driver-gear-12t (Autodesk Fusion 360 design; units mm, degrees)
part number: 2026-11-14-17-19-38-524
part number: 2026-11-14-17-20-11-877
Autodesk Fusion 360 part; units mm, degrees
(part 1 of 5)
sketch "Sketch1" plane through (0, 0, 0) normal (0, 0, 1) x (1, 0, 0) in component "Component"
  spline S0 degree 5 poles (5.75544, -0.790203) (5.755494, -0.79021) (5.755609, -0.790225) (5.755801, -0.790248) (5.756096, -0.790283) (5.756529, -0.790332) (5.757027, -0.790387) (5.75759, -0.790448) (5.758217, -0.790513) (5.758907, -0.790584) (5.75966, -0.790657) (5.760476, -0.790735) (5.761353, -0.790815) (5.762292, -0.790897) (5.763291, -0.790981) (5.764351, -0.791067) (5.765472, -0.791154) (5.766651, -0.791242) (5.767891, -0.79133) (5.769189, -0.791419) (5.770545, -0.791506) (5.771959, -0.791593) (5.773431, -0.791679) (5.77496, -0.791762) (5.776545, -0.791844) (5.778187, -0.791924) (5.779885, -0.792001) (5.781639, -0.792074) (5.783447, -0.792144) (5.785311, -0.792211) (5.787228, -0.792273) (5.7892, -0.79233) (5.791225, -0.792383) (5.793304, -0.792431) (5.795436, -0.792473) (5.79762, -0.792509) (5.799856, -0.79254) (5.802144, -0.792563) (5.804483, -0.79258) (5.806874, -0.79259) (5.809315, -0.792593) (5.811807, -0.792587) (5.814349, -0.792574) (5.816941, -0.792553) (5.819582, -0.792523) (5.822272, -0.792484) (5.825011, -0.792436) (5.827798, -0.792379) (5.830634, -0.792312) (5.833517, -0.792235) (5.836448, -0.792148) (5.839426, -0.792051) (5.84245, -0.791942) (5.845522, -0.791823) (5.848639, -0.791693) (5.851802, -0.791551) (5.855011, -0.791398) (5.858266, -0.791232) (5.861565, -0.791054) (5.864909, -0.790864) (5.868298, -0.790662) (5.87173, -0.790446) (5.875207, -0.790217) (5.878727, -0.789975) (5.88229, -0.789719) (5.885896, -0.78945) (5.889545, -0.789166) (5.893237, -0.788869) (5.89697, -0.788557) (5.900746, -0.78823) (5.904563, -0.787888) (5.908421, -0.787532) (5.91232, -0.78716) (5.91626, -0.786772) (5.920241, -0.786369) (5.924262, -0.78595) (5.928323, -0.785515) (5.932423, -0.785064) (5.936563, -0.784596) (5.940743, -0.784112) (5.944961, -0.783611) (5.949218, -0.783093) (5.953513, -0.782558) (5.957847, -0.782005) (5.962218, -0.781435) (5.966627, -0.780847) (5.971074, -0.780241) (5.975557, -0.779618) (5.980078, -0.778976) (5.984635, -0.778316) (5.989229, -0.777637) (5.993859, -0.776939) (5.998525, -0.776223) (6.003227, -0.775487) (6.007964, -0.774733) (6.012736, -0.773959) (6.017544, -0.773166) (6.022386, -0.772353) (6.027263, -0.77152) (6.032174, -0.770667) (6.037119, -0.769794) (6.042098, -0.768901) (6.047111, -0.767987) (6.052157, -0.767053) (6.057236, -0.766099) (6.062348, -0.765123) (6.067493, -0.764127) (6.072671, -0.763109) (6.077881, -0.762071) (6.083122, -0.76101) (6.088396, -0.759929) (6.093701, -0.758826) (6.099038, -0.757701) (6.104406, -0.756554) (6.109805, -0.755385) (6.115235, -0.754194) (6.120695, -0.752981) (6.126185, -0.751746) (6.131706, -0.750488) (6.137257, -0.749207) (6.142837, -0.747904) (6.148447, -0.746578) (6.154086, -0.745229) (6.159754, -0.743856) (6.165452, -0.742461) (6.171177, -0.741042) (6.176932, -0.7396) (6.182714, -0.738135) (6.188525, -0.736646) (6.194363, -0.735133) (6.20023, -0.733596) (6.206123, -0.732035) (6.212044, -0.73045) (6.217992, -0.728842) (6.223967, -0.727208) (6.229969, -0.725551) (6.235997, -0.723869) (6.242051, -0.722162) (6.248132, -0.720431) (6.254238, -0.718675) (6.26037, -0.716895) (6.266528, -0.715089) (6.272711, -0.713258) (6.278919, -0.711403) (6.285152, -0.709522) (6.29141, -0.707615) (6.297692, -0.705684) (6.303999, -0.703726) (6.31033, -0.701744) (6.316685, -0.699735) (6.323064, -0.697701) (6.329466, -0.695642) (6.335892, -0.693556) (6.342342, -0.691444) (6.348814, -0.689306) (6.355309, -0.687142) (6.361827, -0.684952) (6.368368, -0.682736) (6.374931, -0.680493) (6.381516, -0.678224) (6.388123, -0.675928) (6.394752, -0.673606) (6.401403, -0.671257) (6.408075, -0.668881) (6.414769, -0.666478) (6.421483, -0.664049) (6.428219, -0.661592) (6.434975, -0.659109) (6.441752, -0.656598) (6.44855, -0.654061) (6.455368, -0.651496) (6.462205, -0.648904) (6.469063, -0.646284) (6.475941, -0.643637) (6.482838, -0.640963) (6.489755, -0.63826) (6.49669, -0.635531) (6.503645, -0.632773) (6.510619, -0.629988) (6.517612, -0.627176) (6.524623, -0.624335) (6.531653, -0.621466) (6.5387, -0.61857) (6.545766, -0.615645) (6.55285, -0.612692) (6.559952, -0.609711) (6.567071, -0.606702) (6.574208, -0.603665) (6.581362, -0.6006) (6.588533, -0.597506) (6.595721, -0.594383) (6.602926, -0.591232) (6.610147, -0.588053) (6.617385, -0.584845) (6.624639, -0.581609) (6.63191, -0.578344) (6.639196, -0.57505) (6.646498, -0.571727) (6.653816, -0.568376) (6.66115, -0.564995) (6.668499, -0.561586) (6.675863, -0.558148) (6.683242, -0.554681) (6.690636, -0.551185) (6.698044, -0.54766) (6.705468, -0.544106) (6.712905, -0.540522) (6.720357, -0.53691) (6.727824, -0.533268) (6.735304, -0.529597) (6.742798, -0.525897) (6.750305, -0.522167) (6.757827, -0.518408) (6.765361, -0.514619) (6.772909, -0.510801) (6.78047, -0.506954) (6.788044, -0.503077) (6.79563, -0.49917) (6.80323, -0.495234) (6.810841, -0.491268) (6.818465, -0.487273) (6.826102, -0.483247) (6.83375, -0.479192) (6.84141, -0.475108) (6.849082, -0.470993) (6.856766, -0.466849) (6.864461, -0.462675) (6.872167, -0.458471) (6.879885, -0.454236) (6.887613, -0.449973) (6.895353, -0.445679) (6.903103, -0.441355) (6.910864, -0.437001) (6.918635, -0.432617) (6.926417, -0.428203) (6.934209, -0.423758) (6.942011, -0.419284) (6.949822, -0.41478) (6.957643, -0.410245) (6.965474, -0.40568) (6.973315, -0.401085) (6.979595, -0.397385) (6.984309, -0.394596) (6.987454, -0.39273) (6.989027, -0.391796) knots 0 0 0 0 0 0 0.00416667 0.00833333 0.0125 0.01666667 0.02083333 0.025 0.02916667 0.03333333 0.0375 0.04166667 0.04583333 0.05 0.05416667 0.05833333 0.0625 0.06666667 0.07083333 0.075 0.07916667 0.08333333 0.0875 0.09166667 0.09583333 0.1 0.10416667 0.10833333 0.1125 0.11666667 0.12083333 0.125 0.12916667 0.13333333 0.1375 0.14166667 0.14583333 0.15 0.15416667 0.15833333 0.1625 0.16666667 0.17083333 0.175 0.17916667 0.18333333 0.1875 0.19166667 0.19583333 0.2 0.20416667 0.20833333 0.2125 0.21666667 0.22083333 0.225 0.22916667 0.23333333 0.2375 0.24166667 0.24583333 0.25 0.25416667 0.25833333 0.2625 0.26666667 0.27083333 0.275 0.27916667 0.28333333 0.2875 0.29166667 0.29583333 0.3 0.30416667 0.30833333 0.3125 0.31666667 0.32083333 0.325 0.32916667 0.33333333 0.3375 0.34166667 0.34583333 0.35 0.35416667 0.35833333 0.3625 0.36666667 0.37083333 0.375 0.37916667 0.38333333 0.3875 0.39166667 0.39583333 0.4 0.40416667 0.40833333 0.4125 0.41666667 0.42083333 0.425 0.42916667 0.43333333 0.4375 0.44166667 0.44583333 0.45 0.45416667 0.45833333 0.4625 0.46666667 0.47083333 0.475 0.47916667 0.48333333 0.4875 0.49166667 0.49583333 0.5 0.50416667 0.50833333 0.5125 0.51666667 0.52083333 0.525 0.52916667 0.53333333 0.5375 0.54166667 0.54583333 0.55 0.55416667 0.55833333 0.5625 0.56666667 0.57083333 0.575 0.57916667 0.58333333 0.5875 0.59166667 0.59583333 0.6 0.60416667 0.60833333 0.6125 0.61666667 0.62083333 0.625 0.62916667 0.63333333 0.6375 0.64166667 0.64583333 0.65 0.65416667 0.65833333 0.6625 0.66666667 0.67083333 0.675 0.67916667 0.68333333 0.6875 0.69166667 0.69583333 0.7 0.70416667 0.70833333 0.7125 0.71666667 0.72083333 0.725 0.72916667 0.73333333 0.7375 0.74166667 0.74583333 0.75 0.75416667 0.75833333 0.7625 0.76666667 0.77083333 0.775 0.77916667 0.78333333 0.7875 0.79166667 0.79583333 0.8 0.80416667 0.80833333 0.8125 0.81666667 0.82083333 0.825 0.82916667 0.83333333 0.8375 0.84166667 0.84583333 0.85 0.85416667 0.85833333 0.8625 0.86666667 0.87083333 0.875 0.87916667 0.88333333 0.8875 0.89166667 0.89583333 0.9 0.90416667 0.90833333 0.9125 0.91666667 0.92083333 0.925 0.92916667 0.93333333 0.9375 0.94166667 0.94583333 0.95 0.95416667 0.95833333 0.9625 0.96666667 0.97083333 0.975 0.97916667 0.98333333 0.9875 0.99166667 0.99583333 1 1 1 1 1 1
  spline S1 degree 5 poles (5.75544, 0.790203) (5.755494, 0.79021) (5.755609, 0.790225) (5.755801, 0.790248) (5.756096, 0.790283) (5.756529, 0.790332) (5.757027, 0.790387) (5.75759, 0.790448) (5.758217, 0.790513) (5.758907, 0.790584) (5.75966, 0.790657) (5.760476, 0.790735) (5.761353, 0.790815) (5.762292, 0.790897) (5.763291, 0.790981) (5.764351, 0.791067) (5.765472, 0.791154) (5.766651, 0.791242) (5.767891, 0.79133) (5.769189, 0.791419) (5.770545, 0.791506) (5.771959, 0.791593) (5.773431, 0.791679) (5.77496, 0.791762) (5.776545, 0.791844) (5.778187, 0.791924) (5.779885, 0.792001) (5.781639, 0.792074) (5.783447, 0.792144) (5.785311, 0.792211) (5.787228, 0.792273) (5.7892, 0.79233) (5.791225, 0.792383) (5.793304, 0.792431) (5.795436, 0.792473) (5.79762, 0.792509) (5.799856, 0.79254) (5.802144, 0.792563) (5.804483, 0.79258) (5.806874, 0.79259) (5.809315, 0.792593) (5.811807, 0.792587) (5.814349, 0.792574) (5.816941, 0.792553) (5.819582, 0.792523) (5.822272, 0.792484) (5.825011, 0.792436) (5.827798, 0.792379) (5.830634, 0.792312) (5.833517, 0.792235) (5.836448, 0.792148) (5.839426, 0.792051) (5.84245, 0.791942) (5.845522, 0.791823) (5.848639, 0.791693) (5.851802, 0.791551) (5.855011, 0.791398) (5.858266, 0.791232) (5.861565, 0.791054) (5.864909, 0.790864) (5.868298, 0.790662) (5.87173, 0.790446) (5.875207, 0.790217) (5.878727, 0.789975) (5.88229, 0.789719) (5.885896, 0.78945) (5.889545, 0.789166) (5.893237, 0.788869) (5.89697, 0.788557) (5.900746, 0.78823) (5.904563, 0.787888) (5.908421, 0.787532) (5.91232, 0.78716) (5.91626, 0.786772) (5.920241, 0.786369) (5.924262, 0.78595) (5.928323, 0.785515) (5.932423, 0.785064) (5.936563, 0.784596) (5.940743, 0.784112) (5.944961, 0.783611) (5.949218, 0.783093) (5.953513, 0.782558) (5.957847, 0.782005) (5.962218, 0.781435) (5.966627, 0.780847) (5.971074, 0.780241) (5.975557, 0.779618) (5.980078, 0.778976) (5.984635, 0.778316) (5.989229, 0.777637) (5.993859, 0.776939) (5.998525, 0.776223) (6.003227, 0.775487) (6.007964, 0.774733) (6.012736, 0.773959) (6.017544, 0.773166) (6.022386, 0.772353) (6.027263, 0.77152) (6.032174, 0.770667) (6.037119, 0.769794) (6.042098, 0.768901) (6.047111, 0.767987) (6.052157, 0.767053) (6.057236, 0.766099) (6.062348, 0.765123) (6.067493, 0.764127) (6.072671, 0.763109) (6.077881, 0.762071) (6.083122, 0.76101) (6.088396, 0.759929) (6.093701, 0.758826) (6.099038, 0.757701) (6.104406, 0.756554) (6.109805, 0.755385) (6.115235, 0.754194) (6.120695, 0.752981) (6.126185, 0.751746) (6.131706, 0.750488) (6.137257, 0.749207) (6.142837, 0.747904) (6.148447, 0.746578) (6.154086, 0.745229) (6.159754, 0.743856) (6.165452, 0.742461) (6.171177, 0.741042) (6.176932, 0.7396) (6.182714, 0.738135) (6.188525, 0.736646) (6.194363, 0.735133) (6.20023, 0.733596) (6.206123, 0.732035) (6.212044, 0.73045) (6.217992, 0.728842) (6.223967, 0.727208) (6.229969, 0.725551) (6.235997, 0.723869) (6.242051, 0.722162) (6.248132, 0.720431) (6.254238, 0.718675) (6.26037, 0.716895) (6.266528, 0.715089) (6.272711, 0.713258) (6.278919, 0.711403) (6.285152, 0.709522) (6.29141, 0.707615) (6.297692, 0.705684) (6.303999, 0.703726) (6.31033, 0.701744) (6.316685, 0.699735) (6.323064, 0.697701) (6.329466, 0.695642) (6.335892, 0.693556) (6.342342, 0.691444) (6.348814, 0.689306) (6.355309, 0.687142) (6.361827, 0.684952) (6.368368, 0.682736) (6.374931, 0.680493) (6.381516, 0.678224) (6.388123, 0.675928) (6.394752, 0.673606) (6.401403, 0.671257) (6.408075, 0.668881) (6.414769, 0.666478) (6.421483, 0.664049) (6.428219, 0.661592) (6.434975, 0.659109) (6.441752, 0.656598) (6.44855, 0.654061) (6.455368, 0.651496) (6.462205, 0.648904) (6.469063, 0.646284) (6.475941, 0.643637) (6.482838, 0.640963) (6.489755, 0.63826) (6.49669, 0.635531) (6.503645, 0.632773) (6.510619, 0.629988) (6.517612, 0.627176) (6.524623, 0.624335) (6.531653, 0.621466) (6.5387, 0.61857) (6.545766, 0.615645) (6.55285, 0.612692) (6.559952, 0.609711) (6.567071, 0.606702) (6.574208, 0.603665) (6.581362, 0.6006) (6.588533, 0.597506) (6.595721, 0.594383) (6.602926, 0.591232) (6.610147, 0.588053) (6.617385, 0.584845) (6.624639, 0.581609) (6.63191, 0.578344) (6.639196, 0.57505) (6.646498, 0.571727) (6.653816, 0.568376) (6.66115, 0.564995) (6.668499, 0.561586) (6.675863, 0.558148) (6.683242, 0.554681) (6.690636, 0.551185) (6.698044, 0.54766) (6.705468, 0.544106) (6.712905, 0.540522) (6.720357, 0.53691) (6.727824, 0.533268) (6.735304, 0.529597) (6.742798, 0.525897) (6.750305, 0.522167) (6.757827, 0.518408) (6.765361, 0.514619) (6.772909, 0.510801) (6.78047, 0.506954) (6.788044, 0.503077) (6.79563, 0.49917) (6.80323, 0.495234) (6.810841, 0.491268) (6.818465, 0.487273) (6.826102, 0.483247) (6.83375, 0.479192) (6.84141, 0.475108) (6.849082, 0.470993) (6.856766, 0.466849) (6.864461, 0.462675) (6.872167, 0.458471) (6.879885, 0.454236) (6.887613, 0.449973) (6.895353, 0.445679) (6.903103, 0.441355) (6.910864, 0.437001) (6.918635, 0.432617) (6.926417, 0.428203) (6.934209, 0.423758) (6.942011, 0.419284) (6.949822, 0.41478) (6.957643, 0.410245) (6.965474, 0.40568) (6.973315, 0.401085) (6.979595, 0.397385) (6.984309, 0.394596) (6.987454, 0.39273) (6.989027, 0.391796) knots 0 0 0 0 0 0 0.00416667 0.00833333 0.0125 0.01666667 0.02083333 0.025 0.02916667 0.03333333 0.0375 0.04166667 0.04583333 0.05 0.05416667 0.05833333 0.0625 0.06666667 0.07083333 0.075 0.07916667 0.08333333 0.0875 0.09166667 0.09583333 0.1 0.10416667 0.10833333 0.1125 0.11666667 0.12083333 0.125 0.12916667 0.13333333 0.1375 0.14166667 0.14583333 0.15 0.15416667 0.15833333 0.1625 0.16666667 0.17083333 0.175 0.17916667 0.18333333 0.1875 0.19166667 0.19583333 0.2 0.20416667 0.20833333 0.2125 0.21666667 0.22083333 0.225 0.22916667 0.23333333 0.2375 0.24166667 0.24583333 0.25 0.25416667 0.25833333 0.2625 0.26666667 0.27083333 0.275 0.27916667 0.28333333 0.2875 0.29166667 0.29583333 0.3 0.30416667 0.30833333 0.3125 0.31666667 0.32083333 0.325 0.32916667 0.33333333 0.3375 0.34166667 0.34583333 0.35 0.35416667 0.35833333 0.3625 0.36666667 0.37083333 0.375 0.37916667 0.38333333 0.3875 0.39166667 0.39583333 0.4 0.40416667 0.40833333 0.4125 0.41666667 0.42083333 0.425 0.42916667 0.43333333 0.4375 0.44166667 0.44583333 0.45 0.45416667 0.45833333 0.4625 0.46666667 0.47083333 0.475 0.47916667 0.48333333 0.4875 0.49166667 0.49583333 0.5 0.50416667 0.50833333 0.5125 0.51666667 0.52083333 0.525 0.52916667 0.53333333 0.5375 0.54166667 0.54583333 0.55 0.55416667 0.55833333 0.5625 0.56666667 0.57083333 0.575 0.57916667 0.58333333 0.5875 0.59166667 0.59583333 0.6 0.60416667 0.60833333 0.6125 0.61666667 0.62083333 0.625 0.62916667 0.63333333 0.6375 0.64166667 0.64583333 0.65 0.65416667 0.65833333 0.6625 0.66666667 0.67083333 0.675 0.67916667 0.68333333 0.6875 0.69166667 0.69583333 0.7 0.70416667 0.70833333 0.7125 0.71666667 0.72083333 0.725 0.72916667 0.73333333 0.7375 0.74166667 0.74583333 0.75 0.75416667 0.75833333 0.7625 0.76666667 0.77083333 0.775 0.77916667 0.78333333 0.7875 0.79166667 0.79583333 0.8 0.80416667 0.80833333 0.8125 0.81666667 0.82083333 0.825 0.82916667 0.83333333 0.8375 0.84166667 0.84583333 0.85 0.85416667 0.85833333 0.8625 0.86666667 0.87083333 0.875 0.87916667 0.88333333 0.8875 0.89166667 0.89583333 0.9 0.90416667 0.90833333 0.9125 0.91666667 0.92083333 0.925 0.92916667 0.93333333 0.9375 0.94166667 0.94583333 0.95 0.95416667 0.95833333 0.9625 0.96666667 0.97083333 0.975 0.97916667 0.98333333 0.9875 0.99166667 0.99583333 1 1 1 1 1 1
  spline S2 degree 5 poles (5.754897, -0.790134) (5.754919, -0.790137) (5.754962, -0.790142) (5.755028, -0.79015) (5.755114, -0.790162) (5.755223, -0.790175) (5.75531, -0.790187) (5.755375, -0.790195) (5.755418, -0.7902) (5.75544, -0.790203) knots 0 0 0 0 0 0 0.2 0.4 0.6 0.8 1 1 1 1 1 1
  spline S3 degree 5 poles (5.754897, 0.790134) (5.754919, 0.790137) (5.754962, 0.790142) (5.755028, 0.79015) (5.755114, 0.790162) (5.755223, 0.790175) (5.75531, 0.790187) (5.755375, 0.790195) (5.755418, 0.7902) (5.75544, 0.790203) knots 0 0 0 0 0 0 0.2 0.4 0.6 0.8 1 1 1 1 1 1
  line L0 (0, 0) -> (5.754897, -0.790134)
  line L1 (0, 0) -> (5.754897, 0.790134)
  arc A0 (6.989027, -0.391796) -> (6.989027, 0.391796) centre (0, 0) ccw
  point P0 (5.75707, -0.790392)
  point P1 (5.75979, -0.790669)
  point P2 (5.763604, -0.791006)
  point P3 (5.768513, -0.791372)
  point P4 (5.774519, -0.791737)
  point P5 (5.781621, -0.792072)
  point P6 (5.789821, -0.792346)
  point P7 (5.799117, -0.792529)
  point P8 (5.809509, -0.79259)
  point P9 (5.820994, -0.792501)
  point P10 (5.833571, -0.792231)
  point P11 (5.847237, -0.79175)
  point P12 (5.861986, -0.791029)
  point P13 (5.877817, -0.790036)
  point P14 (5.894723, -0.788743)
  point P15 (5.912699, -0.78712)
  point P16 (5.931739, -0.785137)
  point P17 (5.951837, -0.782765)
  point P18 (5.972984, -0.779974)
  point P19 (5.995174, -0.776735)
  point P20 (6.018398, -0.77302)
  point P21 (6.042646, -0.768798)
  point P22 (6.067908, -0.764042)
  point P23 (6.094176, -0.758723)
  point P24 (6.121436, -0.752811)
  point P25 (6.149679, -0.74628)
  point P26 (6.178892, -0.739101)
  point P27 (6.209063, -0.731246)
  point P28 (6.240177, -0.722688)
  point P29 (6.272222, -0.713399)
  point P30 (6.305182, -0.703353)
  point P31 (6.339044, -0.692521)
  point P32 (6.373791, -0.680879)
  point P33 (6.409407, -0.668399)
  point P34 (6.445876, -0.655056)
  point P35 (6.483181, -0.640824)
  point P36 (6.521303, -0.625677)
  point P37 (6.560225, -0.609591)
  point P38 (6.599928, -0.592541)
  point P39 (6.640392, -0.574502)
  point P40 (6.681597, -0.55545)
  point P41 (6.723524, -0.535362)
  point P42 (6.766151, -0.514215)
  point P43 (6.809457, -0.491985)
  point P44 (6.85342, -0.46865)
  point P45 (6.898018, -0.444188)
  point P46 (6.943228, -0.418577)
  point P47 (5.75707, 0.790392)
  point P48 (5.75979, 0.790669)
  point P49 (5.763604, 0.791006)
  point P50 (5.768513, 0.791372)
  point P51 (5.774519, 0.791737)
  point P52 (5.781621, 0.792072)
  point P53 (5.789821, 0.792346)
  point P54 (5.799117, 0.792529)
  point P55 (5.809509, 0.79259)
  point P56 (5.820994, 0.792501)
  point P57 (5.833571, 0.792231)
  point P58 (5.847237, 0.79175)
  point P59 (5.861986, 0.791029)
  point P60 (5.877817, 0.790036)
  point P61 (5.894723, 0.788743)
  point P62 (5.912699, 0.78712)
  point P63 (5.931739, 0.785137)
  point P64 (5.951837, 0.782765)
  point P65 (5.972984, 0.779974)
  point P66 (5.995174, 0.776735)
  point P67 (6.018398, 0.77302)
  point P68 (6.042646, 0.768798)
  point P69 (6.067908, 0.764042)
  point P70 (6.094176, 0.758723)
  point P71 (6.121436, 0.752811)
  point P72 (6.149679, 0.74628)
  point P73 (6.178892, 0.739101)
  point P74 (6.209063, 0.731246)
  point P75 (6.240177, 0.722688)
  point P76 (6.272222, 0.713399)
  point P77 (6.305182, 0.703353)
  point P78 (6.339044, 0.692521)
  point P79 (6.373791, 0.680879)
  point P80 (6.409407, 0.668399)
  point P81 (6.445876, 0.655056)
  point P82 (6.483181, 0.640824)
  point P83 (6.521303, 0.625677)
  point P84 (6.560225, 0.609591)
  point P85 (6.599928, 0.592541)
  point P86 (6.640392, 0.574502)
  point P87 (6.681597, 0.55545)
  point P88 (6.723524, 0.535362)
  point P89 (6.766151, 0.514215)
  point P90 (6.809457, 0.491985)
  point P91 (6.85342, 0.46865)
  point P92 (6.898018, 0.444188)
  point P93 (6.943228, 0.418577)
sketch "Sketch2" plane through (0, 0, 0) normal (0, 0, 1) x (1, 0, 0) in component "Component"
  circle A0 centre (0, 0) radius 4.75
extrude "Extrude1" add sketch "Sketch2" along normal blind 6 contours A0 picked at (0.37743, 0.961676) makes body 1 in component "Component"
extrude "Extrude2" add sketch "Sketch1" along normal blind 6 separate body contours S0 S1 L0 L1 A0 picked at (3.83696, 0) makes body 2 in component "Component"
pattern_circular "C-Pattern1" count 12 over 360 about axis through (0, 0, 1.75) along (0, 0, 1) of "Extrude2" makes body 3 at (1.793153, 0.731128, 2) makes body 4 at (0.731128, 1.793153, 2) makes body 5 at (0.263401, 1.91848, 2) makes body 6 at (-0.731128, 1.793153, 2) makes body 7 at (-1.793153, 0.731128, 2) makes body 8 at (-1.91848, 0.263401, 2) makes body 9 at (-1.793153, -0.731128, 2) makes body 10 at (-1.187352, -1.529752, 2) makes body 11 at (-0.263401, -1.91848, 2) makes body 12 at (0.731128, -1.793153, 2) makes body 13 at (1.529752, -1.187352, 2) in component "Component"
combine "Combine1" operation add target body 1 tool bodies 2 3 4 5 6 7 8 9 10 11 12 13 in component "Component"
sketch "Sketch3" plane through (0, 0, 0) normal (0, 0, 1) x (1, 0, 0) in component "Component"
  line L0 (0, 0) -> (51.187501, 0) construction
  line L1 (51.187501, 0) -> (51.187501, 3) construction
  line L2 (51.187501, 3) -> (0, 3) construction
  line L3 (0, 3) -> (0, 0) construction
  constraint perpendicular L0 L1
  constraint parallel L0 L2
  constraint parallel L1 L3
sketch "Sketch4" plane through (0, 0, 6) normal (0, 0, 1) x (-1, 0, 0) in component "Component"
  arc A0 (-4.398439, 1.793385) -> (-4.705853, 0.646102) centre (0, 0) ccw
  line L0 (-4.705853, 0.646102) -> (-5.754897, 0.790134)
  line L1 (-5.754897, 0.790134) -> (-5.75544, 0.790203)
  spline S0 degree 5 poles (-5.75544, 0.790203) (-5.755494, 0.79021) (-5.755609, 0.790225) (-5.755801, 0.790248) (-5.756096, 0.790283) (-5.756529, 0.790332) (-5.757027, 0.790387) (-5.75759, 0.790448) (-5.758217, 0.790513) (-5.758907, 0.790584) (-5.75966, 0.790657) (-5.760476, 0.790735) (-5.761353, 0.790815) (-5.762292, 0.790897) (-5.763291, 0.790981) (-5.764351, 0.791067) (-5.765472, 0.791154) (-5.766651, 0.791242) (-5.767891, 0.79133) (-5.769189, 0.791419) (-5.770545, 0.791506) (-5.771959, 0.791593) (-5.773431, 0.791679) (-5.77496, 0.791762) (-5.776545, 0.791844) (-5.778187, 0.791924) (-5.779885, 0.792001) (-5.781639, 0.792074) (-5.783447, 0.792144) (-5.785311, 0.792211) (-5.787228, 0.792273) (-5.7892, 0.79233) (-5.791225, 0.792383) (-5.793304, 0.792431) (-5.795436, 0.792473) (-5.79762, 0.792509) (-5.799856, 0.79254) (-5.802144, 0.792563) (-5.804483, 0.79258) (-5.806874, 0.79259) (-5.809315, 0.792593) (-5.811807, 0.792587) (-5.814349, 0.792574) (-5.816941, 0.792553) (-5.819582, 0.792523) (-5.822272, 0.792484) (-5.825011, 0.792436) (-5.827798, 0.792379) (-5.830634, 0.792312) (-5.833517, 0.792235) (-5.836448, 0.792148) (-5.839426, 0.792051) (-5.84245, 0.791942) (-5.845522, 0.791823) (-5.848639, 0.791693) (-5.851802, 0.791551) (-5.855011, 0.791398) (-5.858266, 0.791232) (-5.861565, 0.791054) (-5.864909, 0.790864) (-5.868298, 0.790662) (-5.87173, 0.790446) (-5.875207, 0.790217) (-5.878727, 0.789975) (-5.88229, 0.789719) (-5.885896, 0.78945) (-5.889545, 0.789166) (-5.893237, 0.788869) (-5.89697, 0.788557) (-5.900746, 0.78823) (-5.904563, 0.787888) (-5.908421, 0.787532) (-5.91232, 0.78716) (-5.91626, 0.786772) (-5.920241, 0.786369) (-5.924262, 0.78595) (-5.928323, 0.785515) (-5.932423, 0.785064) (-5.936563, 0.784596) (-5.940743, 0.784112) (-5.944961, 0.783611) (-5.949218, 0.783093) (-5.953513, 0.782558) (-5.957847, 0.782005) (-5.962218, 0.781435) (-5.966627, 0.780847) (-5.971074, 0.780241) (-5.975557, 0.779618) (-5.980078, 0.778976) (-5.984635, 0.778316) (-5.989229, 0.777637) (-5.993859, 0.776939) (-5.998525, 0.776223) (-6.003227, 0.775487) (-6.007964, 0.774733) (-6.012736, 0.773959) (-6.017544, 0.773166) (-6.022386, 0.772353) (-6.027263, 0.77152) (-6.032174, 0.770667) (-6.037119, 0.769794) (-6.042098, 0.768901) (-6.047111, 0.767987) (-6.052157, 0.767053) (-6.057236, 0.766099) (-6.062348, 0.765123) (-6.067493, 0.764127) (-6.072671, 0.763109) (-6.077881, 0.762071) (-6.083122, 0.76101) (-6.088396, 0.759929) (-6.093701, 0.758826) (-6.099038, 0.757701) (-6.104406, 0.756554) (-6.109805, 0.755385) (-6.115235, 0.754194) (-6.120695, 0.752981) (-6.126185, 0.751746) (-6.131706, 0.750488) (-6.137257, 0.749207) (-6.142837, 0.747904) (-6.148447, 0.746578) (-6.154086, 0.745229) (-6.159754, 0.743856) (-6.165452, 0.742461) (-6.171177, 0.741042) (-6.176932, 0.7396) (-6.182714, 0.738135) (-6.188525, 0.736646) (-6.194363, 0.735133) (-6.20023, 0.733596) (-6.206123, 0.732035) (-6.212044, 0.73045) (-6.217992, 0.728842) (-6.223967, 0.727208) (-6.229969, 0.725551) (-6.235997, 0.723869) (-6.242051, 0.722162) (-6.248132, 0.720431) (-6.254238, 0.718675) (-6.26037, 0.716895) (-6.266528, 0.715089) (-6.272711, 0.713258) (-6.278919, 0.711403) (-6.285152, 0.709522) (-6.29141, 0.707615) (-6.297692, 0.705684) (-6.303999, 0.703726) (-6.31033, 0.701744) (-6.316685, 0.699735) (-6.323064, 0.697701) (-6.329466, 0.695642) (-6.335892, 0.693556) (-6.342342, 0.691444) (-6.348814, 0.689306) (-6.355309, 0.687142) (-6.361827, 0.684952) (-6.368368, 0.682736) (-6.374931, 0.680493) (-6.381516, 0.678224) (-6.388123, 0.675928) (-6.394752, 0.673606) (-6.401403, 0.671257) (-6.408075, 0.668881) (-6.414769, 0.666478) (-6.421483, 0.664049) (-6.428219, 0.661592) (-6.434975, 0.659109) (-6.441752, 0.656598) (-6.44855, 0.654061) (-6.455368, 0.651496) (-6.462205, 0.648904) (-6.469063, 0.646284) (-6.475941, 0.643637) (-6.482838, 0.640963) (-6.489755, 0.63826) (-6.49669, 0.635531) (-6.503645, 0.632773) (-6.510619, 0.629988) (-6.517612, 0.627176) (-6.524623, 0.624335) (-6.531653, 0.621466) (-6.5387, 0.61857) (-6.545766, 0.615645) (-6.55285, 0.612692) (-6.559952, 0.609711) (-6.567071, 0.606702) (-6.574208, 0.603665) (-6.581362, 0.6006) (-6.588533, 0.597506) (-6.595721, 0.594383) (-6.602926, 0.591232) (-6.610147, 0.588053) (-6.617385, 0.584845) (-6.624639, 0.581609) (-6.63191, 0.578344) (-6.639196, 0.57505) (-6.646498, 0.571727) (-6.653816, 0.568376) (-6.66115, 0.564995) (-6.668499, 0.561586) (-6.675863, 0.558148) (-6.683242, 0.554681) (-6.690636, 0.551185) (-6.698044, 0.54766) (-6.705468, 0.544106) (-6.712905, 0.540522) (-6.720357, 0.53691) (-6.727824, 0.533268) (-6.735304, 0.529597) (-6.742798, 0.525897) (-6.750305, 0.522167) (-6.757827, 0.518408) (-6.765361, 0.514619) (-6.772909, 0.510801) (-6.78047, 0.506954) (-6.788044, 0.503077) (-6.79563, 0.49917) (-6.80323, 0.495234) (-6.810841, 0.491268) (-6.818465, 0.487273) (-6.826102, 0.483247) (-6.83375, 0.479192) (-6.84141, 0.475108) (-6.849082, 0.470993) (-6.856766, 0.466849) (-6.864461, 0.462675) (-6.872167, 0.458471) (-6.879885, 0.454236) (-6.887613, 0.449973) (-6.895353, 0.445679) (-6.903103, 0.441355) (-6.910864, 0.437001) (-6.918635, 0.432617) (-6.926417, 0.428203) (-6.934209, 0.423758) (-6.942011, 0.419284) (-6.949822, 0.41478) (-6.957643, 0.410245) (-6.965474, 0.40568) (-6.973315, 0.401085) (-6.979595, 0.397385) (-6.984309, 0.394596) (-6.987454, 0.39273) (-6.989027, 0.391796) knots 0 0 0 0 0 0 0.00416667 0.00833333 0.0125 0.01666667 0.02083333 0.025 0.02916667 0.03333333 0.0375 0.04166667 0.04583333 0.05 0.05416667 0.05833333 0.0625 0.06666667 0.07083333 0.075 0.07916667 0.08333333 0.0875 0.09166667 0.09583333 0.1 0.10416667 0.10833333 0.1125 0.11666667 0.12083333 0.125 0.12916667 0.13333333 0.1375 0.14166667 0.14583333 0.15 0.15416667 0.15833333 0.1625 0.16666667 0.17083333 0.175 0.17916667 0.18333333 0.1875 0.19166667 0.19583333 0.2 0.20416667 0.20833333 0.2125 0.21666667 0.22083333 0.225 0.22916667 0.23333333 0.2375 0.24166667 0.24583333 0.25 0.25416667 0.25833333 0.2625 0.26666667 0.27083333 0.275 0.27916667 0.28333333 0.2875 0.29166667 0.29583333 0.3 0.30416667 0.30833333 0.3125 0.31666667 0.32083333 0.325 0.32916667 0.33333333 0.3375 0.34166667 0.34583333 0.35 0.35416667 0.35833333 0.3625 0.36666667 0.37083333 0.375 0.37916667 0.38333333 0.3875 0.39166667 0.39583333 0.4 0.40416667 0.40833333 0.4125 0.41666667 0.42083333 0.425 0.42916667 0.43333333 0.4375 0.44166667 0.44583333 0.45 0.45416667 0.45833333 0.4625 0.46666667 0.47083333 0.475 0.47916667 0.48333333 0.4875 0.49166667 0.49583333 0.5 0.50416667 0.50833333 0.5125 0.51666667 0.52083333 0.525 0.52916667 0.53333333 0.5375 0.54166667 0.54583333 0.55 0.55416667 0.55833333 0.5625 0.56666667 0.57083333 0.575 0.57916667 0.58333333 0.5875 0.59166667 0.59583333 0.6 0.60416667 0.60833333 0.6125 0.61666667 0.62083333 0.625 0.62916667 0.63333333 0.6375 0.64166667 0.64583333 0.65 0.65416667 0.65833333 0.6625 0.66666667 0.67083333 0.675 0.67916667 0.68333333 0.6875 0.69166667 0.69583333 0.7 0.70416667 0.70833333 0.7125 0.71666667 0.72083333 0.725 0.72916667 0.73333333 0.7375 0.74166667 0.74583333 0.75 0.75416667 0.75833333 0.7625 0.76666667 0.77083333 0.775 0.77916667 0.78333333 0.7875 0.79166667 0.79583333 0.8 0.80416667 0.80833333 0.8125 0.81666667 0.82083333 0.825 0.82916667 0.83333333 0.8375 0.84166667 0.84583333 0.85 0.85416667 0.85833333 0.8625 0.86666667 0.87083333 0.875 0.87916667 0.88333333 0.8875 0.89166667 0.89583333 0.9 0.90416667 0.90833333 0.9125 0.91666667 0.92083333 0.925 0.92916667 0.93333333 0.9375 0.94166667 0.94583333 0.95 0.95416667 0.95833333 0.9625 0.96666667 0.97083333 0.975 0.97916667 0.98333333 0.9875 0.99166667 0.99583333 1 1 1 1 1 1
  arc A1 (-6.989027, 0.391796) -> (-6.989027, -0.391796) centre (0, 0) ccw
  spline S1 degree 5 poles (-6.989027, -0.391796) (-6.987454, -0.39273) (-6.984309, -0.394596) (-6.979595, -0.397385) (-6.973315, -0.401085) (-6.965474, -0.40568) (-6.957643, -0.410245) (-6.949822, -0.41478) (-6.942011, -0.419284) (-6.934209, -0.423758) (-6.926417, -0.428203) (-6.918635, -0.432617) (-6.910864, -0.437001) (-6.903103, -0.441355) (-6.895353, -0.445679) (-6.887613, -0.449973) (-6.879885, -0.454236) (-6.872167, -0.458471) (-6.864461, -0.462675) (-6.856766, -0.466849) (-6.849082, -0.470993) (-6.84141, -0.475108) (-6.83375, -0.479192) (-6.826102, -0.483247) (-6.818465, -0.487273) (-6.810841, -0.491268) (-6.80323, -0.495234) (-6.79563, -0.49917) (-6.788044, -0.503077) (-6.78047, -0.506954) (-6.772909, -0.510801) (-6.765361, -0.514619) (-6.757827, -0.518408) (-6.750305, -0.522167) (-6.742798, -0.525897) (-6.735304, -0.529597) (-6.727824, -0.533268) (-6.720357, -0.53691) (-6.712905, -0.540522) (-6.705468, -0.544106) (-6.698044, -0.54766) (-6.690636, -0.551185) (-6.683242, -0.554681) (-6.675863, -0.558148) (-6.668499, -0.561586) (-6.66115, -0.564995) (-6.653816, -0.568376) (-6.646498, -0.571727) (-6.639196, -0.57505) (-6.63191, -0.578344) (-6.624639, -0.581609) (-6.617385, -0.584845) (-6.610147, -0.588053) (-6.602926, -0.591232) (-6.595721, -0.594383) (-6.588533, -0.597506) (-6.581362, -0.6006) (-6.574208, -0.603665) (-6.567071, -0.606702) (-6.559952, -0.609711) (-6.55285, -0.612692) (-6.545766, -0.615645) (-6.5387, -0.61857) (-6.531653, -0.621466) (-6.524623, -0.624335) (-6.517612, -0.627176) (-6.510619, -0.629988) (-6.503645, -0.632773) (-6.49669, -0.635531) (-6.489755, -0.63826) (-6.482838, -0.640963) (-6.475941, -0.643637) (-6.469063, -0.646284) (-6.462205, -0.648904) (-6.455368, -0.651496) (-6.44855, -0.654061) (-6.441752, -0.656598) (-6.434975, -0.659109) (-6.428219, -0.661592) (-6.421483, -0.664049) (-6.414769, -0.666478) (-6.408075, -0.668881) (-6.401403, -0.671257) (-6.394752, -0.673606) (-6.388123, -0.675928) (-6.381516, -0.678224) (-6.374931, -0.680493) (-6.368368, -0.682736) (-6.361827, -0.684952) (-6.355309, -0.687142) (-6.348814, -0.689306) (-6.342342, -0.691444) (-6.335892, -0.693556) (-6.329466, -0.695642) (-6.323064, -0.697701) (-6.316685, -0.699735) (-6.31033, -0.701744) (-6.303999, -0.703726) (-6.297692, -0.705684) (-6.29141, -0.707615) (-6.285152, -0.709522) (-6.278919, -0.711403) (-6.272711, -0.713258) (-6.266528, -0.715089) (-6.26037, -0.716895) (-6.254238, -0.718675) (-6.248132, -0.720431) (-6.242051, -0.722162) (-6.235997, -0.723869) (-6.229969, -0.725551) (-6.223967, -0.727208) (-6.217992, -0.728842) (-6.212044, -0.73045) (-6.206123, -0.732035) (-6.20023, -0.733596) (-6.194363, -0.735133) (-6.188525, -0.736646) (-6.182714, -0.738135) (-6.176932, -0.7396) (-6.171177, -0.741042) (-6.165452, -0.742461) (-6.159754, -0.743856) (-6.154086, -0.745229) (-6.148447, -0.746578) (-6.142837, -0.747904) (-6.137257, -0.749207) (-6.131706, -0.750488) (-6.126185, -0.751746) (-6.120695, -0.752981) (-6.115235, -0.754194) (-6.109805, -0.755385) (-6.104406, -0.756554) (-6.099038, -0.757701) (-6.093701, -0.758826) (-6.088396, -0.759929) (-6.083122, -0.76101) (-6.077881, -0.762071) (-6.072671, -0.763109) (-6.067493, -0.764127) (-6.062348, -0.765123) (-6.057236, -0.766099) (-6.052157, -0.767053) (-6.047111, -0.767987) (-6.042098, -0.768901) (-6.037119, -0.769794) (-6.032174, -0.770667) (-6.027263, -0.77152) (-6.022386, -0.772353) (-6.017544, -0.773166) (-6.012736, -0.773959) (-6.007964, -0.774733) (-6.003227, -0.775487) (-5.998525, -0.776223) (-5.993859, -0.776939) (-5.989229, -0.777637) (-5.984635, -0.778316) (-5.980078, -0.778976) (-5.975557, -0.779618) (-5.971074, -0.780241) (-5.966627, -0.780847) (-5.962218, -0.781435) (-5.957847, -0.782005) (-5.953513, -0.782558) (-5.949218, -0.783093) (-5.944961, -0.783611) (-5.940743, -0.784112) (-5.936563, -0.784596) (-5.932423, -0.785064) (-5.928323, -0.785515) (-5.924262, -0.78595) (-5.920241, -0.786369) (-5.91626, -0.786772) (-5.91232, -0.78716) (-5.908421, -0.787532) (-5.904563, -0.787888) (-5.900746, -0.78823) (-5.89697, -0.788557) (-5.893237, -0.788869) (-5.889545, -0.789166) (-5.885896, -0.78945) (-5.88229, -0.789719) (-5.878727, -0.789975) (-5.875207, -0.790217) (-5.87173, -0.790446) (-5.868298, -0.790662) (-5.864909, -0.790864) (-5.861565, -0.791054) (-5.858266, -0.791232) (-5.855011, -0.791398) (-5.851802, -0.791551) (-5.848639, -0.791693) (-5.845522, -0.791823) (-5.84245, -0.791942) (-5.839426, -0.792051) (-5.836448, -0.792148) (-5.833517, -0.792235) (-5.830634, -0.792312) (-5.827798, -0.792379) (-5.825011, -0.792436) (-5.822272, -0.792484) (-5.819582, -0.792523) (-5.816941, -0.792553) (-5.814349, -0.792574) (-5.811807, -0.792587) (-5.809315, -0.792593) (-5.806874, -0.79259) (-5.804483, -0.79258) (-5.802144, -0.792563) (-5.799856, -0.79254) (-5.79762, -0.792509) (-5.795436, -0.792473) (-5.793304, -0.792431) (-5.791225, -0.792383) (-5.7892, -0.79233) (-5.787228, -0.792273) (-5.785311, -0.792211) (-5.783447, -0.792144) (-5.781639, -0.792074) (-5.779885, -0.792001) (-5.778187, -0.791924) (-5.776545, -0.791844) (-5.77496, -0.791762) (-5.773431, -0.791679) (-5.771959, -0.791593) (-5.770545, -0.791506) (-5.769189, -0.791419) (-5.767891, -0.79133) (-5.766651, -0.791242) (-5.765472, -0.791154) (-5.764351, -0.791067) (-5.763291, -0.790981) (-5.762292, -0.790897) (-5.761353, -0.790815) (-5.760476, -0.790735) (-5.75966, -0.790657) (-5.758907, -0.790584) (-5.758217, -0.790513) (-5.75759, -0.790448) (-5.757027, -0.790387) (-5.756529, -0.790332) (-5.756096, -0.790283) (-5.755801, -0.790248) (-5.755609, -0.790225) (-5.755494, -0.79021) (-5.75544, -0.790203) knots -1 -1 -1 -1 -1 -1 -0.99583333 -0.99166667 -0.9875 -0.98333333 -0.97916667 -0.975 -0.97083333 -0.96666667 -0.9625 -0.95833333 -0.95416667 -0.95 -0.94583333 -0.94166667 -0.9375 -0.93333333 -0.92916667 -0.925 -0.92083333 -0.91666667 -0.9125 -0.90833333 -0.90416667 -0.9 -0.89583333 -0.89166667 -0.8875 -0.88333333 -0.87916667 -0.875 -0.87083333 -0.86666667 -0.8625 -0.85833333 -0.85416667 -0.85 -0.84583333 -0.84166667 -0.8375 -0.83333333 -0.82916667 -0.825 -0.82083333 -0.81666667 -0.8125 -0.80833333 -0.80416667 -0.8 -0.79583333 -0.79166667 -0.7875 -0.78333333 -0.77916667 -0.775 -0.77083333 -0.76666667 -0.7625 -0.75833333 -0.75416667 -0.75 -0.74583333 -0.74166667 -0.7375 -0.73333333 -0.72916667 -0.725 -0.72083333 -0.71666667 -0.7125 -0.70833333 -0.70416667 -0.7 -0.69583333 -0.69166667 -0.6875 -0.68333333 -0.67916667 -0.675 -0.67083333 -0.66666667 -0.6625 -0.65833333 -0.65416667 -0.65 -0.64583333 -0.64166667 -0.6375 -0.63333333 -0.62916667 -0.625 -0.62083333 -0.61666667 -0.6125 -0.60833333 -0.60416667 -0.6 -0.59583333 -0.59166667 -0.5875 -0.58333333 -0.57916667 -0.575 -0.57083333 -0.56666667 -0.5625 -0.55833333 -0.55416667 -0.55 -0.54583333 -0.54166667 -0.5375 -0.53333333 -0.52916667 -0.525 -0.52083333 -0.51666667 -0.5125 -0.50833333 -0.50416667 -0.5 -0.49583333 -0.49166667 -0.4875 -0.48333333 -0.47916667 -0.475 -0.47083333 -0.46666667 -0.4625 -0.45833333 -0.45416667 -0.45 -0.44583333 -0.44166667 -0.4375 -0.43333333 -0.42916667 -0.425 -0.42083333 -0.41666667 -0.4125 -0.40833333 -0.40416667 -0.4 -0.39583333 -0.39166667 -0.3875 -0.38333333 -0.37916667 -0.375 -0.37083333 -0.36666667 -0.3625 -0.35833333 -0.35416667 -0.35 -0.34583333 -0.34166667 -0.3375 -0.33333333 -0.32916667 -0.325 -0.32083333 -0.31666667 -0.3125 -0.30833333 -0.30416667 -0.3 -0.29583333 -0.29166667 -0.2875 -0.28333333 -0.27916667 -0.275 -0.27083333 -0.26666667 -0.2625 -0.25833333 -0.25416667 -0.25 -0.24583333 -0.24166667 -0.2375 -0.23333333 -0.22916667 -0.225 -0.22083333 -0.21666667 -0.2125 -0.20833333 -0.20416667 -0.2 -0.19583333 -0.19166667 -0.1875 -0.18333333 -0.17916667 -0.175 -0.17083333 -0.16666667 -0.1625 -0.15833333 -0.15416667 -0.15 -0.14583333 -0.14166667 -0.1375 -0.13333333 -0.12916667 -0.125 -0.12083333 -0.11666667 -0.1125 -0.10833333 -0.10416667 -0.1 -0.09583333 -0.09166667 -0.0875 -0.08333333 -0.07916667 -0.075 -0.07083333 -0.06666667 -0.0625 -0.05833333 -0.05416667 -0.05 -0.04583333 -0.04166667 -0.0375 -0.03333333 -0.02916667 -0.025 -0.02083333 -0.01666667 -0.0125 -0.00833333 -0.00416667 0 0 0 0 0 0
  line L2 (-5.75544, -0.790203) -> (-5.754897, -0.790134)
  line L3 (-5.754897, -0.790134) -> (-4.705853, -0.646102)
  arc A2 (-4.705853, -0.646102) -> (-4.398439, -1.793385) centre (0, 0) ccw
  line L4 (-4.398439, -1.793385) -> (-5.378954, -2.193173)
  line L5 (-5.378954, -2.193173) -> (-5.379459, -2.193384)
  spline S2 degree 5 poles (-5.379459, -2.193384) (-5.379509, -2.193405) (-5.379616, -2.19345) (-5.379794, -2.193526) (-5.380067, -2.193643) (-5.380467, -2.193817) (-5.380926, -2.194018) (-5.381443, -2.194247) (-5.382019, -2.194504) (-5.382652, -2.194788) (-5.383341, -2.195101) (-5.384086, -2.195442) (-5.384885, -2.195811) (-5.385739, -2.196209) (-5.386647, -2.196636) (-5.387608, -2.197091) (-5.388622, -2.197576) (-5.389688, -2.19809) (-5.390805, -2.198633) (-5.391973, -2.199206) (-5.393192, -2.199808) (-5.39446, -2.20044) (-5.395777, -2.201102) (-5.397143, -2.201794) (-5.398557, -2.202515) (-5.400019, -2.203268) (-5.401528, -2.20405) (-5.403083, -2.204863) (-5.404684, -2.205707) (-5.406331, -2.206581) (-5.408023, -2.207486) (-5.40976, -2.208422) (-5.41154, -2.209389) (-5.413364, -2.210387) (-5.415231, -2.211416) (-5.417141, -2.212477) (-5.419092, -2.213569) (-5.421086, -2.214692) (-5.42312, -2.215847) (-5.425195, -2.217034) (-5.427311, -2.218252) (-5.429466, -2.219503) (-5.431661, -2.220785) (-5.433895, -2.2221) (-5.436167, -2.223446) (-5.438478, -2.224825) (-5.440826, -2.226236) (-5.443211, -2.227679) (-5.445633, -2.229155) (-5.448092, -2.230663) (-5.450586, -2.232203) (-5.453116, -2.233777) (-5.455682, -2.235383) (-5.458282, -2.237022) (-5.460917, -2.238693) (-5.463585, -2.240398) (-5.466288, -2.242135) (-5.469023, -2.243906) (-5.471792, -2.245709) (-5.474593, -2.247546) (-5.477426, -2.249416) (-5.480291, -2.251319) (-5.483187, -2.253255) (-5.486114, -2.255225) (-5.489072, -2.257228) (-5.492061, -2.259264) (-5.495079, -2.261334) (-5.498127, -2.263438) (-5.501204, -2.265575) (-5.50431, -2.267746) (-5.507445, -2.26995) (-5.510608, -2.272188) (-5.513799, -2.27446) (-5.517018, -2.276766) (-5.520264, -2.279105) (-5.523536, -2.281478) (-5.526836, -2.283885) (-5.530161, -2.286326) (-5.533513, -2.288801) (-5.53689, -2.29131) (-5.540293, -2.293854) (-5.54372, -2.296431) (-5.547172, -2.299042) (-5.550649, -2.301687) (-5.55415, -2.304367) (-5.557674, -2.30708) (-5.561222, -2.309828) (-5.564793, -2.31261) (-5.568387, -2.315426) (-5.572004, -2.318277) (-5.575643, -2.321161) (-5.579304, -2.32408) (-5.582987, -2.327034) (-5.586691, -2.330022) (-5.590416, -2.333044) (-5.594162, -2.3361) (-5.597929, -2.339191) (-5.601716, -2.342316) (-5.605523, -2.345476) (-5.609349, -2.34867) (-5.613196, -2.351898) (-5.617061, -2.355161) (-5.620945, -2.358459) (-5.624848, -2.361791) (-5.62877, -2.365157) (-5.632709, -2.368558) (-5.636667, -2.371994) (-5.640642, -2.375463) (-5.644634, -2.378968) (-5.648644, -2.382507) (-5.65267, -2.38608) (-5.656713, -2.389688) (-5.660772, -2.393331) (-5.664848, -2.397008) (-5.668939, -2.40072) (-5.673046, -2.404466) (-5.677168, -2.408247) (-5.681305, -2.412062) (-5.685457, -2.415912) (-5.689624, -2.419796) (-5.693805, -2.423715) (-5.698, -2.427668) (-5.702209, -2.431656) (-5.706432, -2.435679) (-5.710668, -2.439736) (-5.714918, -2.443827) (-5.71918, -2.447953) (-5.723455, -2.452114) (-5.727743, -2.456309) (-5.732042, -2.460538) (-5.736354, -2.464802) (-5.740678, -2.469101) (-5.745013, -2.473433) (-5.74936, -2.477801) (-5.753718, -2.482203) (-5.758087, -2.486639) (-5.762466, -2.49111) (-5.766856, -2.495615) (-5.771256, -2.500154) (-5.775667, -2.504728) (-5.780087, -2.509336) (-5.784517, -2.513979) (-5.788956, -2.518656) (-5.793404, -2.523367) (-5.797862, -2.528112) (-5.802328, -2.532892) (-5.806803, -2.537706) (-5.811286, -2.542554) (-5.815778, -2.547437) (-5.820277, -2.552354) (-5.824785, -2.557305) (-5.829299, -2.56229) (-5.833822, -2.567309) (-5.838351, -2.572363) (-5.842887, -2.57745) (-5.84743, -2.582572) (-5.85198, -2.587728) (-5.856536, -2.592917) (-5.861098, -2.598141) (-5.865667, -2.603399) (-5.870241, -2.608691) (-5.874821, -2.614016) (-5.879406, -2.619376) (-5.883996, -2.62477) (-5.888592, -2.630197) (-5.893192, -2.635658) (-5.897797, -2.641154) (-5.902407, -2.646683) (-5.90702, -2.652245) (-5.911638, -2.657842) (-5.91626, -2.663472) (-5.920886, -2.669136) (-5.925515, -2.674833) (-5.930148, -2.680564) (-5.934784, -2.686329) (-5.939423, -2.692128) (-5.944064, -2.697959) (-5.948709, -2.703825) (-5.953356, -2.709724) (-5.958005, -2.715656) (-5.962657, -2.721622) (-5.96731, -2.727621) (-5.971966, -2.733653) (-5.976622, -2.739719) (-5.981281, -2.745818) (-5.985941, -2.75195) (-5.990602, -2.758116) (-5.995264, -2.764315) (-5.999926, -2.770546) (-6.00459, -2.776811) (-6.009253, -2.78311) (-6.013918, -2.789441) (-6.018582, -2.795805) (-6.023246, -2.802202) (-6.02791, -2.808632) (-6.032574, -2.815095) (-6.037237, -2.82159) (-6.0419, -2.828119) (-6.046562, -2.83468) (-6.051223, -2.841274) (-6.055882, -2.847901) (-6.060541, -2.854561) (-6.065198, -2.861253) (-6.069853, -2.867977) (-6.074507, -2.874735) (-6.079158, -2.881524) (-6.083808, -2.888347) (-6.088455, -2.895201) (-6.0931, -2.902088) (-6.097743, -2.909007) (-6.102382, -2.915959) (-6.107019, -2.922943) (-6.111653, -2.929959) (-6.116284, -2.937007) (-6.120912, -2.944088) (-6.125536, -2.9512) (-6.130157, -2.958345) (-6.134774, -2.965521) (-6.139387, -2.97273) (-6.143996, -2.97997) (-6.148601, -2.987242) (-6.153201, -2.994546) (-6.157797, -3.001882) (-6.162389, -3.00925) (-6.166976, -3.016649) (-6.171558, -3.02408) (-6.176135, -3.031542) (-6.180707, -3.039036) (-6.185273, -3.046562) (-6.189834, -3.054119) (-6.19439, -3.061707) (-6.19894, -3.069327) (-6.203484, -3.076978) (-6.208022, -3.084661) (-6.212555, -3.092374) (-6.21708, -3.100119) (-6.2216, -3.107895) (-6.226112, -3.115701) (-6.230618, -3.123539) (-6.235117, -3.131408) (-6.23961, -3.139308) (-6.243199, -3.145652) (-6.245887, -3.150425) (-6.247678, -3.153612) (-6.248573, -3.155208) knots 0 0 0 0 0 0 0.00416667 0.00833333 0.0125 0.01666667 0.02083333 0.025 0.02916667 0.03333333 0.0375 0.04166667 0.04583333 0.05 0.05416667 0.05833333 0.0625 0.06666667 0.07083333 0.075 0.07916667 0.08333333 0.0875 0.09166667 0.09583333 0.1 0.10416667 0.10833333 0.1125 0.11666667 0.12083333 0.125 0.12916667 0.13333333 0.1375 0.14166667 0.14583333 0.15 0.15416667 0.15833333 0.1625 0.16666667 0.17083333 0.175 0.17916667 0.18333333 0.1875 0.19166667 0.19583333 0.2 0.20416667 0.20833333 0.2125 0.21666667 0.22083333 0.225 0.22916667 0.23333333 0.2375 0.24166667 0.24583333 0.25 0.25416667 0.25833333 0.2625 0.26666667 0.27083333 0.275 0.27916667 0.28333333 0.2875 0.29166667 0.29583333 0.3 0.30416667 0.30833333 0.3125 0.31666667 0.32083333 0.325 0.32916667 0.33333333 0.3375 0.34166667 0.34583333 0.35 0.35416667 0.35833333 0.3625 0.36666667 0.37083333 0.375 0.37916667 0.38333333 0.3875 0.39166667 0.39583333 0.4 0.40416667 0.40833333 0.4125 0.41666667 0.42083333 0.425 0.42916667 0.43333333 0.4375 0.44166667 0.44583333 0.45 0.45416667 0.45833333 0.4625 0.46666667 0.47083333 0.475 0.47916667 0.48333333 0.4875 0.49166667 0.49583333 0.5 0.50416667 0.50833333 0.5125 0.51666667 0.52083333 0.525 0.52916667 0.53333333 0.5375 0.54166667 0.54583333 0.55 0.55416667 0.55833333 0.5625 0.56666667 0.57083333 0.575 0.57916667 0.58333333 0.5875 0.59166667 0.59583333 0.6 0.60416667 0.60833333 0.6125 0.61666667 0.62083333 0.625 0.62916667 0.63333333 0.6375 0.64166667 0.64583333 0.65 0.65416667 0.65833333 0.6625 0.66666667 0.67083333 0.675 0.67916667 0.68333333 0.6875 0.69166667 0.69583333 0.7 0.70416667 0.70833333 0.7125 0.71666667 0.72083333 0.725 0.72916667 0.73333333 0.7375 0.74166667 0.74583333 0.75 0.75416667 0.75833333 0.7625 0.76666667 0.77083333 0.775 0.77916667 0.78333333 0.7875 0.79166667 0.79583333 0.8 0.80416667 0.80833333 0.8125 0.81666667 0.82083333 0.825 0.82916667 0.83333333 0.8375 0.84166667 0.84583333 0.85 0.85416667 0.85833333 0.8625 0.86666667 0.87083333 0.875 0.87916667 0.88333333 0.8875 0.89166667 0.89583333 0.9 0.90416667 0.90833333 0.9125 0.91666667 0.92083333 0.925 0.92916667 0.93333333 0.9375 0.94166667 0.94583333 0.95 0.95416667 0.95833333 0.9625 0.96666667 0.97083333 0.975 0.97916667 0.98333333 0.9875 0.99166667 0.99583333 1 1 1 1 1 1
  arc A3 (-6.248573, -3.155208) -> (-5.856777, -3.833819) centre (0, 0) ccw